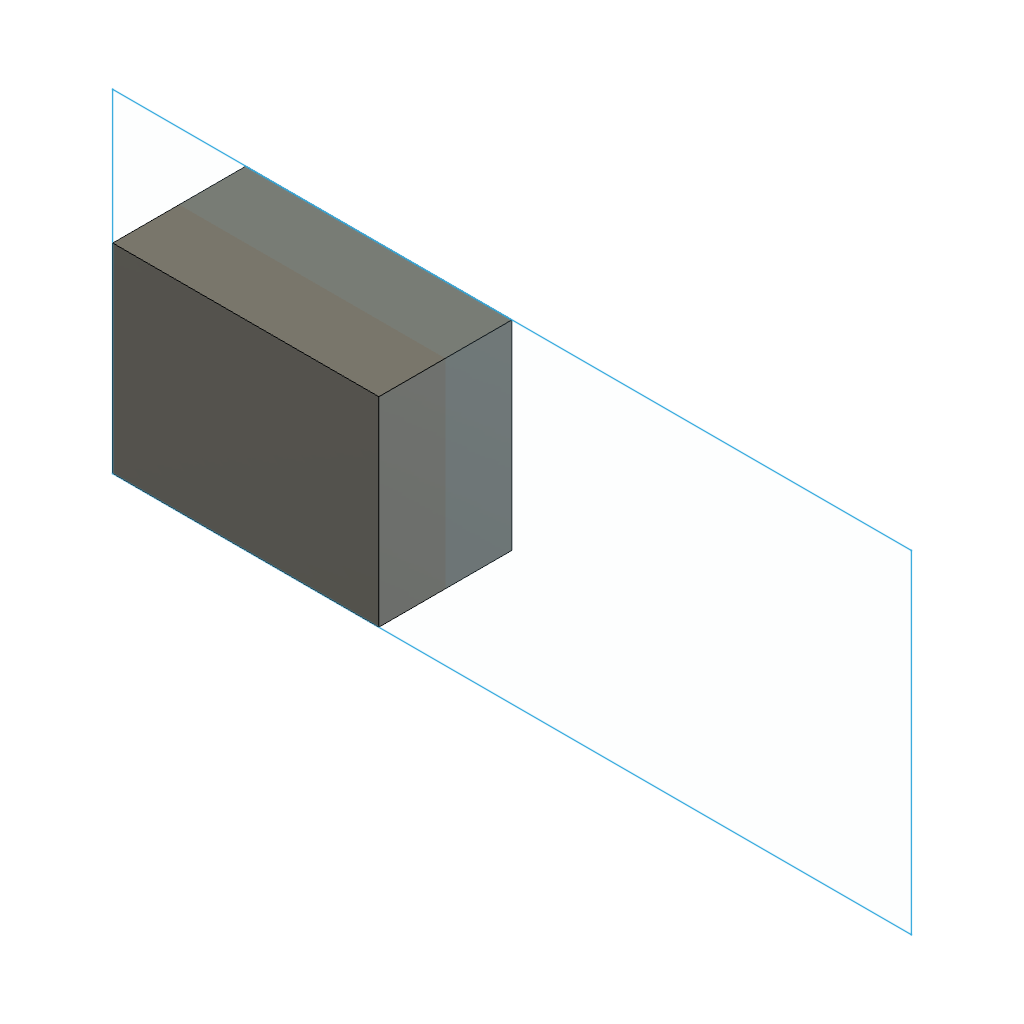
full_profile_one_body (Autodesk Fusion 360 design; units mm, degrees)
part number: 2026-10-21-16-22-05-289
Autodesk Fusion 360 part; units mm, degrees
sketch "OwnedProfileSplitBlockSketch_0_full_profile_one_body" plane through (0, 0, 0) normal (0, 0, 1) x (1, 0, 0)
  line L0 (0, 0) -> (40, 0)
  line L1 (40, 0) -> (40, 30)
  line L2 (40, 30) -> (0, 30)
  line L3 (0, 30) -> (0, 0)
extrude "OwnedProfileSplitBlockExtrude_0_full_profile_one_body" add sketch "OwnedProfileSplitBlockSketch_0_full_profile_one_body" along normal blind 20
ref_plane "WorkPlane1" through (0, 0, 10) normal (0, 0, 1) x (1, 0, 0)
sketch "OwnedSplitProfileBoundary_full_profile_one_body" plane through (0, 0, 10) normal (0, 0, 1) x (1, 0, 0)
  line L0 (-10, -10) -> (110, -10)
  line L1 (110, -10) -> (110, 40)
  line L2 (110, 40) -> (-10, 40)
  line L3 (-10, 40) -> (-10, -10)
named bodies: "OwnedProfileSplitBlock_0_full_profile_one_body"
